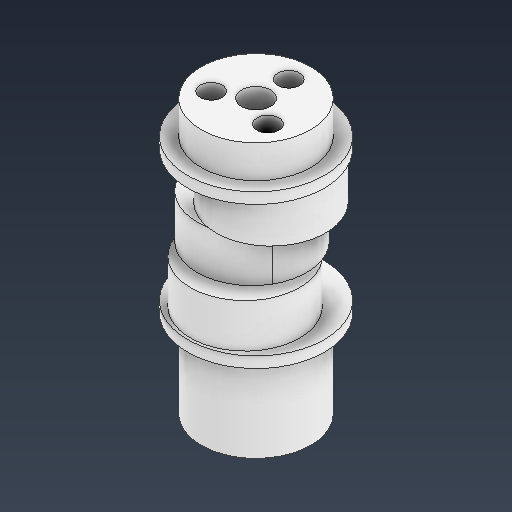
# Autodesk Inventor part: shaft
Saved by Autodesk Inventor 2026.2 (Build 302298010, 298A)
## iProperties
Created: 2026-04-09
Part Number: shaft
Material: PLA
Document SubType Name: Modeling
Designer: khw
Density: 1.24 g/cm^3
Appearance: 일반
Description: 편심축, 분리식
Mass: 16.6492 g
Surface Area: 74.1329 cm^2
Volume: 13.4268 cm^3
Author: khw
Autodesk Inventor part; units mm, degrees
ref_plane "YZ Plane" through (0, 0, 0) normal (1, 0, 0) x (0, 1, 0)
ref_plane "XZ Plane" through (0, 0, 0) normal (0, 1, 0) x (-1, 0, 0)
ref_plane "XY Plane" through (0, 0, 0) normal (0, 0, 1) x (1, 0, 0)
sketch "스케치1" plane through (0, 0, 0) normal (0, 1, 0) x (-1, 0, 0)
  circle A0 centre (0, 0) radius 10
  dimension "d0" = 20
  constraints: 1 centre point, 1 coincident
  measures "d0" diameter of A0
extrude "돌출1" add sketch "스케치1" along normal blind 6
sketch "스케치2" plane through (0, 6, 0) normal (0, 1, 0) x (1, 0, 0)
  circle A0 centre (0, 0) radius 12.5
  dimension "d3" = 25
  constraints: 1 centre point, 1 coincident
  measures "d3" diameter of A0
extrude "돌출2" add sketch "스케치2" along normal blind 2
sketch "스케치3" plane through (0, 8, 0) normal (0, 1, 0) x (1, 0, 0)
  line L0 (0, 0) -> (0, -2)
  circle A0 centre (0, -2) radius 10
  dimension "d6" = 2
  dimension "d7" = 20
  constraints: 2 end point, 1 centre point, 1 coincident, 1 vertical
  measures "d6" distance of L0.start L0.end
  measures "d7" diameter of A0
extrude "돌출3" add sketch "스케치3" along normal blind 8
sketch "스케치4" plane through (0, 16, 2) normal (0, 1, 0) x (1, 0, 0)
  line L0 (0, 2) -> (0, -1.0112)
  line L1 (0, -1.0112) -> (0, 2)
  line L2 (0, 2) -> (-1.7321, 3)
  circle A0 centre (-1.7321, 3) radius 10
  dimension "d10" = 2
  dimension "d11" = 120
  dimension "d12" = 20
  constraints: 6 end point, 1 centre point, 1 coincident, 1 collinear, 1 vertical
  measures "d10" distance of L0.start L2.end
  measures "d11" angle of L0 L2
  measures "d12" diameter of A0
extrude "돌출4" add sketch "스케치4" along normal blind 8
sketch "스케치5" plane through (-1.7321, 24, -1) normal (0, 1, 0) x (1, 0, 0)
  circle A0 centre (1.7321, -1) radius 10 projected
  line L0 (1.7321, -1) -> (1.7321, -4.0505)
  line L1 (1.7321, -1) -> (3.4641, 0)
  circle A1 centre (3.4641, 0) radius 10
  dimension "d15" = 2
  dimension "d16" = 120
  dimension "d17" = 20
  constraints: 4 end point, 1 centre point, 1 coincident, 1 vertical
  measures "d15" distance of L0.start L1.end
  measures "d16" angle of L1 L0
  measures "d17" diameter of A1
extrude "돌출5" add sketch "스케치5" along normal blind 8 contours A0 A1 | A0 A1 picked at (4.7941, 1.5274) picked at (10.1614, 5.4207)
sketch "스케치6" plane through (1.7321, 32, -1) normal (0, 1, 0) x (1, 0, 0)
  circle A0 centre (-1.7321, -1) radius 10 construction
  circle A1 centre (-1.7321, -1) radius 12.5
  dimension "d20" = 25
  constraints: 1 centre point, 1 coincident
  measures "d20" diameter of A1
extrude "돌출6" add sketch "스케치6" along normal blind 2
sketch "스케치7" plane through (0, 34, 0) normal (0, 1, 0) x (1, 0, 0)
  circle A0 centre (0, 0) radius 10
  dimension "d23" = 20
  constraints: 1 centre point, 1 coincident
  measures "d23" diameter of A0
extrude "돌출7" add sketch "스케치7" along normal blind 6
sketch "스케치8" plane through (0, 40, 0) normal (0, 1, 0) x (1, 0, 0)
  circle A0 centre (0, 0) radius 2.65
  dimension "d26" = 5.3
  constraints: 1 centre point, 1 coincident
  measures "d26" diameter of A0
extrude "돌출8" cut sketch "스케치8" against normal through all
sketch "스케치9" plane through (0, 40, 0) normal (0, 1, 0) x (1, 0, 0)
  line L0 (0, 0) -> (0, 6) construction
  circle A0 centre (0, 6) radius 2
  circle A1 centre (0, 0) radius 2.65 projected
  circle A2 centre (0, 0) radius 10 projected
  circle A3 centre (-5.1962, -3) radius 2
  circle A4 centre (5.1962, -3) radius 2
  dimension "d29" = 4
  dimension "d32" = 360
  dimension "d34" = 6
  constraints: 3 centre point, 2 end point, 1 coincident, 1 vertical, 7 other
  measures "d29" diameter of A0
  measures "d34" distance of L0.start L0.end
extrude "돌출9" cut sketch "스케치9" against normal through all contours A0 | A3 | A4
sketch "스케치10" plane through (0, 0, 0) normal (0, -1, 0) x (1, 0, 0)
  circle A0 centre (0, -6) radius 2 projected
  circle A1 centre (-5.1962, 3) radius 2 projected
  circle A2 centre (5.1962, 3) radius 2 projected
  circle A3 centre (0, 0) radius 2.65 projected
  circle A4 centre (0, 0) radius 10 projected
extrude "돌출10" add sketch "스케치10" along normal blind 10
